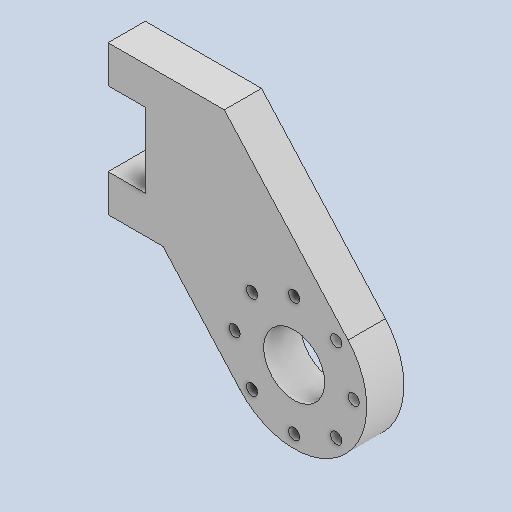
# Autodesk Inventor part: ShoulderSideL
Saved by Autodesk Inventor 2025.2 (Build 292293000, 293)
## iProperties
Created: 2025-06-27
Part Number: ShoulderSideL
Material: Generic
Document SubType Name: Modeling
Designer: ricoa
Density: 1 g/cm^3
Appearance: Default
Author: ricoa
Autodesk Inventor part; units mm, degrees
ref_plane "YZ Plane" through (0, 0, 0) normal (1, 0, 0) x (0, 1, 0)
ref_plane "XZ Plane" through (0, 0, 0) normal (0, 1, 0) x (-1, 0, 0)
ref_plane "XY Plane" through (0, 0, 0) normal (0, 0, 1) x (1, 0, 0)
sketch "Sketch1" plane through (0, 0, 0) normal (0, 0, 1) x (1, 0, 0)
  arc A0 (-7.2471, -6.5224) -> (7.2471, 6.5224) centre (0, 0) ccw
  circle A1 centre (0, 0) radius 4 projected
  circle A2 centre (-5.6569, 5.6569) radius 0.75 projected
  circle A3 centre (-8, 0) radius 0.75 projected
  circle A4 centre (-5.6569, -5.6569) radius 0.75 projected
  circle A5 centre (0, -8) radius 0.75 projected
  circle A6 centre (5.6569, -5.6569) radius 0.75 projected
  circle A7 centre (8, 0) radius 0.75 projected
  circle A8 centre (5.6569, 5.6569) radius 0.75 projected
  circle A9 centre (0, 8) radius 0.75 projected
  circle A10 centre (0, 0) radius 4.1
  line L0 (0, 0) -> (0, 15) construction
  line L1 (0, 15) -> (-20, 15) construction
  line L2 (-20, 15) -> (-25, 15) construction
  line L3 (-20, 15) -> (-20, 25) construction
  line L4 (-20, 15) -> (-20, 5) construction
  line L5 (-14.25, -33.25) -> (-14.25, 9.25) projected
  line L6 (-20, 5) -> (-17.6173, 5)
  line L7 (7.2471, 6.5224) -> (2.8839, 11.3705)
  line L8 (2.8839, 11.3705) -> (-9.3827, 25)
  line L9 (-9.3827, 25) -> (-20, 25)
  line L10 (-20, 25) -> (-25, 25)
  line L11 (-25, 25) -> (-25, 20)
  line L12 (-25, 20) -> (-20, 20)
  line L13 (-20, 20) -> (-20, 15)
  line L14 (-20, 15) -> (-25, 15)
  line L15 (-25, 10) -> (-20, 10)
  line L16 (-20, 15) -> (-20, 10)
  line L17 (-25, 10) -> (-25, 5)
  line L18 (-25, 5) -> (-20, 5)
  line L19 (-7.2471, -6.5224) -> (-17.6173, 5)
  point P0 (0, 0)
  dimension "d0" = 8.2
  dimension "d1" = 15
  dimension "d2" = 20
  dimension "d3" = 5
  dimension "d4" = 10
  constraints: 38 end point, 4 perpendicular, 4 vertical, 3 collinear, 3 point on line, 2 centre point, 2 horizontal, 2 midpoint, 2 point on circle, 2 tangent, 1 coincident
  measures "d0" diameter of A10
  measures "d1" distance of L0.start L0.end
  measures "d2" distance of L0.end L1.end
  measures "d3" distance of L1.end L2.end
  measures "d4" distance of L1.end L3.end
extrude "Extrusion1" add sketch "Sketch1" along normal blind 5 contours L19 L6 L18 L17 L15 L16 L13 L12 L11 L10 L9 L8 L7 A0
body "Solid1"
